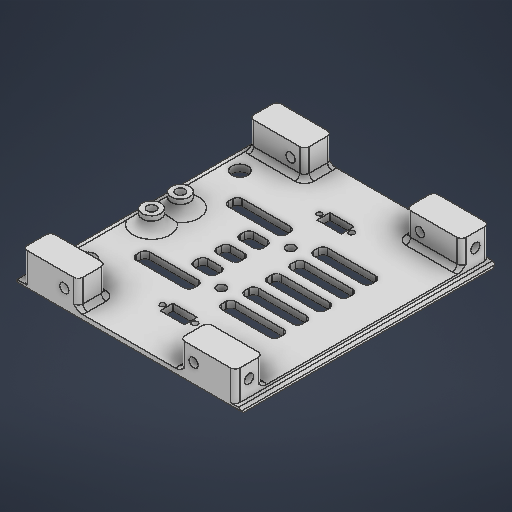
# Autodesk Inventor part: side
Saved by Autodesk Inventor 2026.2 (Build 302298010, 298A)
## iProperties
Created: 2026-05-12
Part Number: side
Material: 일반
Document SubType Name: Modeling
Designer: work
Density: 1 g/cm^3
Appearance: 기본값
Author: work
Autodesk Inventor part; units mm, degrees
ref_plane "YZ Plane" through (0, 0, 0) normal (1, 0, 0) x (0, 1, 0)
ref_plane "XZ Plane" through (0, 0, 0) normal (0, 1, 0) x (-1, 0, 0)
sketch "스케치1" plane through (0, 0, 0) normal (0, 1, 0) x (-1, 0, 0)
  line L0 (92, 0) -> (0, 0)
  line L1 (0, 0) -> (0, -110)
  line L2 (0, -110) -> (92, -110)
  line L3 (92, -110) -> (92, 0)
  line L4 (86, -104) -> (6, -104) construction
  line L5 (6, -104) -> (6, -6) construction
  line L6 (6, -6) -> (86, -6) construction
  line L7 (86, -6) -> (86, -104) construction
  line L8 (0, 0) -> (24, 0)
  line L9 (24, 0) -> (24, -12)
  line L10 (24, -12) -> (0, -12)
  line L11 (0, -12) -> (0, 0)
  line L12 (92, 0) -> (68, 0)
  line L13 (68, 0) -> (68, -12)
  line L14 (68, -12) -> (92, -12)
  line L15 (92, -12) -> (92, 0)
  line L16 (92, -110) -> (68, -110)
  line L17 (68, -110) -> (68, -98)
  line L18 (68, -98) -> (92, -98)
  line L19 (92, -98) -> (92, -110)
  line L20 (0, -110) -> (24, -110)
  line L21 (24, -110) -> (24, -98)
  line L22 (24, -98) -> (0, -98)
  line L23 (0, -98) -> (0, -110)
  line L24 (92, -55) -> (0, -55) construction
  line L25 (46, 0) -> (46, -110) construction
  circle A0 centre (46, -40) radius 2
  circle A1 centre (46, -70) radius 2
  circle A2 centre (86, -88) radius 3.5
  circle A3 centre (86, -22) radius 3.5
  line L26 (52, -32) -> (77, -32)
  line L27 (77, -32) -> (77, -38)
  line L28 (77, -38) -> (52, -38)
  line L29 (52, -38) -> (52, -32)
  line L30 (52, -48) -> (52, -42)
  line L31 (77, -48) -> (52, -48)
  line L32 (52, -42) -> (77, -42)
  line L33 (77, -42) -> (77, -48)
  line L34 (52, -58) -> (52, -52)
  line L35 (77, -58) -> (52, -58)
  line L36 (52, -52) -> (77, -52)
  line L37 (77, -52) -> (77, -58)
  line L38 (52, -68) -> (52, -62)
  line L39 (77, -68) -> (52, -68)
  line L40 (52, -62) -> (77, -62)
  line L41 (77, -62) -> (77, -68)
  line L42 (52, -78) -> (52, -72)
  line L43 (77, -78) -> (52, -78)
  line L44 (52, -72) -> (77, -72)
  line L45 (77, -72) -> (77, -78)
  line L46 (40, -32) -> (15, -32)
  line L47 (15, -32) -> (15, -38)
  line L48 (15, -38) -> (40, -38)
  line L49 (40, -38) -> (40, -32)
  line L50 (40, -48) -> (40, -42)
  line L51 (15, -48) -> (40, -48)
  line L52 (40, -42) -> (15, -42)
  line L53 (15, -42) -> (15, -48)
  line L54 (40, -58) -> (40, -52)
  line L55 (15, -58) -> (40, -58)
  line L56 (40, -52) -> (15, -52)
  line L57 (15, -52) -> (15, -58)
  line L58 (40, -68) -> (40, -62)
  line L59 (15, -68) -> (40, -68)
  line L60 (40, -62) -> (15, -62)
  line L61 (15, -62) -> (15, -68)
  line L62 (40, -78) -> (40, -72)
  line L63 (15, -78) -> (40, -78)
  line L64 (40, -72) -> (15, -72)
  line L65 (15, -72) -> (15, -78)
  point P0 (86, -55)
  point P1 (77, -55)
  point P2 (0, -98)
  dimension "d0" = 6
  dimension "d1" = 6
  dimension "d2" = 24
  dimension "d3" = 12
  dimension "d4" = 24
  dimension "d5" = 12
  dimension "d6" = 24
  dimension "d7" = 12
  dimension "d8" = 24
  dimension "d9" = 12
  dimension "d10" = 98
  dimension "d12" = 80
  dimension "d13" = 6
  dimension "d14" = 6
  dimension "d15" = 4
  dimension "d16" = 4
  dimension "d17" = 30
  dimension "d18" = 15
  dimension "d19" = 7
  dimension "d20" = 10
  dimension "d21" = 7
  dimension "d22" = 10
  dimension "d23" = 25
  dimension "d24" = 6
  dimension "d27" = 10
  dimension "d32" = 15
  constraints: 132 end point, 20 symmetric about line, 14 parallel, 7 horizontal, 7 perpendicular, 6 midpoint, 5 point on line, 4 centre point, 1 coincident, 1 vertical, 32 other
  measures "d0" distance between parallel lines of L1 L5
  measures "d1" distance between parallel lines of L0 L6
  measures "d2" distance of L9.end L10.end
  measures "d3" distance of L8.end L9.end
  measures "d4" distance of L14.end L13.end
  measures "d5" distance of L13.end L12.end
  measures "d6" distance of L17.end L18.end
  measures "d7" distance of L16.end L17.end
  measures "d8" distance of L22.end L21.end
  measures "d9" distance of L21.end L20.end
  measures "d10" distance of L4.start L6.end
  measures "d12" distance of L6.end L5.end
  measures "d13" distance from line of L3 point (86, -55)
  measures "d14" distance between parallel lines of L2 L4
  measures "d15" diameter of A0
  measures "d16" diameter of A1
  measures "d17" distance of A1.centre A0.centre
  measures "d18" distance from line of L24 A1.centre
  measures "d19" diameter of A2
  measures "d20" distance from line of L18 A2.centre
  measures "d21" diameter of A3
  measures "d22" distance from line of L14 A3.centre
  measures "d23" distance of L27.end L28.end
  measures "d24" distance of L26.end L27.end
  measures "d27" distance of L28.end L30.start
  measures "d32" distance between parallel lines of L3 L37
extrude "돌출1" add sketch "스케치1" along normal blind 3 contours L13 L14 L3 L18 L17 L2 L21 L22 L1 L10 L9 L0
extrude "돌출2" add sketch "스케치1" along normal blind 15 contours L3 L14 L13 L0 | L9 L10 L1 L0 | L3 L2 L17 L18 | L22 L21 L2 L1
sketch "스케치2" plane through (0, 0, 0) normal (0, -1, 0) x (1, 0, 0)
  line L0 (-24, -98) -> (-24, -110) projected
  line L1 (-24, -110) -> (-68, -110) projected
  line L2 (-68, -110) -> (-68, -98) projected
  line L3 (-68, -98) -> (-92, -98) projected
  line L4 (-92, -98) -> (-92, -12) projected
  line L5 (-92, -12) -> (-68, -12) projected
  line L6 (-68, -12) -> (-68, 0) projected
  line L7 (-68, 0) -> (-24, 0) projected
  line L8 (-24, 0) -> (-24, -12) projected
  line L9 (-24, -12) -> (0, -12) projected
  line L10 (0, -12) -> (0, -98) projected
  line L11 (0, -98) -> (-24, -98) projected
  circle A0 centre (-46, -40) radius 2 projected
  circle A1 centre (-46, -70) radius 2 projected
  circle A2 centre (-86, -88) radius 3.5 projected
  circle A3 centre (-86, -22) radius 3.5 projected
  line L12 (-15, -32) -> (-40, -32) projected
  line L13 (-40, -32) -> (-40, -38) projected
  line L14 (-40, -38) -> (-15, -38) projected
  line L15 (-15, -38) -> (-15, -32) projected
  line L16 (-15, -48) -> (-15, -42) projected
  line L17 (-15, -42) -> (-40, -42) projected
  line L18 (-40, -42) -> (-40, -48) projected
  line L19 (-40, -48) -> (-15, -48) projected
  line L20 (-40, -72) -> (-40, -78) projected
  line L21 (-40, -78) -> (-15, -78) projected
  line L22 (-15, -78) -> (-15, -72) projected
  line L23 (-15, -72) -> (-40, -72) projected
  line L24 (-40, -62) -> (-40, -68) projected
  line L25 (-40, -68) -> (-15, -68) projected
  line L26 (-15, -68) -> (-15, -62) projected
  line L27 (-15, -62) -> (-40, -62) projected
  line L28 (-40, -58) -> (-15, -58) projected
  line L29 (-15, -58) -> (-15, -52) projected
  line L30 (-15, -52) -> (-40, -52) projected
  line L31 (-40, -52) -> (-40, -58) projected
  line L32 (-52, -78) -> (-52, -72) projected
  line L33 (-52, -72) -> (-77, -72) projected
  line L34 (-77, -72) -> (-77, -78) projected
  line L35 (-77, -78) -> (-52, -78) projected
  line L36 (-52, -68) -> (-52, -62) projected
  line L37 (-52, -62) -> (-77, -62) projected
  line L38 (-77, -62) -> (-77, -68) projected
  line L39 (-77, -68) -> (-52, -68) projected
  line L40 (-52, -58) -> (-52, -52) projected
  line L41 (-52, -52) -> (-77, -52) projected
  line L42 (-77, -52) -> (-77, -58) projected
  line L43 (-77, -58) -> (-52, -58) projected
  line L44 (-52, -48) -> (-52, -42) projected
  line L45 (-52, -42) -> (-77, -42) projected
  line L46 (-77, -42) -> (-77, -48) projected
  line L47 (-77, -48) -> (-52, -48) projected
  line L48 (-52, -32) -> (-77, -32) projected
  line L49 (-77, -32) -> (-77, -38) projected
  line L50 (-77, -38) -> (-52, -38) projected
  line L51 (-52, -38) -> (-52, -32) projected
  line L52 (0, 0) -> (0, -110) projected
  line L53 (-92, 0) -> (0, 0) projected
  line L54 (-92, -110) -> (-92, 0) projected
  line L55 (0, -110) -> (-92, -110) projected
  circle A4 centre (-46, -40) radius 2 projected
  circle A5 centre (-46, -70) radius 2 projected
  circle A6 centre (-86, -88) radius 3.5 projected
  circle A7 centre (-86, -22) radius 3.5 projected
  line L56 (-15, -32) -> (-40, -32) projected
  line L57 (-15, -38) -> (-15, -32) projected
  line L58 (-40, -38) -> (-15, -38) projected
  line L59 (-40, -32) -> (-40, -38) projected
  line L60 (-15, -48) -> (-15, -42) projected
  line L61 (-40, -48) -> (-15, -48) projected
  line L62 (-40, -42) -> (-40, -48) projected
  line L63 (-15, -42) -> (-40, -42) projected
  line L64 (-40, -72) -> (-40, -78) projected
  line L65 (-15, -72) -> (-40, -72) projected
  line L66 (-15, -78) -> (-15, -72) projected
  line L67 (-40, -78) -> (-15, -78) projected
  line L68 (-40, -62) -> (-40, -68) projected
  line L69 (-15, -62) -> (-40, -62) projected
  line L70 (-15, -68) -> (-15, -62) projected
  line L71 (-40, -68) -> (-15, -68) projected
  line L72 (-40, -58) -> (-15, -58) projected
  line L73 (-40, -52) -> (-40, -58) projected
  line L74 (-15, -52) -> (-40, -52) projected
  line L75 (-15, -58) -> (-15, -52) projected
  line L76 (-52, -78) -> (-52, -72) projected
  line L77 (-77, -78) -> (-52, -78) projected
  line L78 (-77, -72) -> (-77, -78) projected
  line L79 (-52, -72) -> (-77, -72) projected
  line L80 (-52, -68) -> (-52, -62) projected
  line L81 (-77, -68) -> (-52, -68) projected
  line L82 (-77, -62) -> (-77, -68) projected
  line L83 (-52, -62) -> (-77, -62) projected
  line L84 (-52, -58) -> (-52, -52) projected
  line L85 (-77, -58) -> (-52, -58) projected
  line L86 (-77, -52) -> (-77, -58) projected
  line L87 (-52, -52) -> (-77, -52) projected
  line L88 (-52, -48) -> (-52, -42) projected
  line L89 (-77, -48) -> (-52, -48) projected
  line L90 (-77, -42) -> (-77, -48) projected
  line L91 (-52, -42) -> (-77, -42) projected
  line L92 (-52, -32) -> (-77, -32) projected
  line L93 (-52, -38) -> (-52, -32) projected
  line L94 (-77, -38) -> (-52, -38) projected
  line L95 (-77, -32) -> (-77, -38) projected
  line L96 (-94.5, -110) -> (2.5, -110)
  line L97 (2.5, -110) -> (2.5, 0)
  line L98 (2.5, 0) -> (-94.5, 0)
  line L99 (-94.5, 0) -> (-94.5, -110)
  dimension "d37" = 2.5
  dimension "d38" = 2.5
  constraints: 8 end point, 2 parallel, 2 point on line, 1 horizontal, 1 perpendicular
  measures "d37" distance between parallel lines of L97 L52
  measures "d38" distance between parallel lines of L99 L4
extrude "돌출3" add sketch "스케치2" against normal blind 2 contours L10 L52 L98 L97 L96 | L96 L99 L98 L54 L4
sketch "스케치3" plane through (-92, 3, -12) normal (-1, 0, 0) x (0, 0, 1)
  line L0 (-98, -1) -> (12, -1) projected
  line L1 (12, -1) -> (12, 12) projected
  line L2 (0, 12) -> (12, 12) projected
  line L3 (0, 0) -> (0, 12) projected
  line L4 (-86, 0) -> (0, 0) projected
  line L5 (-86, 0) -> (-86, 12) projected
  line L6 (-98, 12) -> (-86, 12) projected
  line L7 (-98, -1) -> (-98, 12) projected
  line L8 (12, 0) -> (0, 12) construction
  line L9 (0, 0) -> (12, 12) construction
  circle A0 centre (6, 6) radius 2
  line L10 (-86, 0) -> (0, 0) projected
  line L11 (-43, 0) -> (-43, 34.867) construction
  line L12 (-86, 0) -> (-98, 12) construction
  line L13 (-86, 12) -> (-98, 0) construction
  circle A1 centre (-92, 6) radius 2
  point P0 (12, -3)
  dimension "d41" = 4
  dimension "d42" = 4
  constraints: 10 end point, 4 midpoint, 2 centre point, 2 perpendicular, 2 point on line, 1 vertical
  measures "d41" diameter of A0
  measures "d42" diameter of A1
extrude "돌출4" cut sketch "스케치3" against normal blind 12 contours A0 | A1
sketch "스케치4" plane through (-68, 3, 0) normal (0, 0, 1) x (1, 0, 0)
  circle A0 centre (-6, 6) radius 2
  line L0 (-24, 12) -> (0, 12) projected
  line L1 (0, 0) -> (0, 12) projected
  point P0 (68, -3)
  dimension "d45" = 4
  dimension "d46" = 6
  dimension "d47" = 6
  constraints: 1 centre point
  measures "d45" diameter of A0
  measures "d46" distance from line of L0 A0.centre
  measures "d47" distance from line of L1 A0.centre
extrude "돌출5" cut sketch "스케치4" against normal through all
ref_plane "작업 평면1" through (-46, 0, -110) normal (-1, 0, 0) x (0, 0, 1)
mirror "미러1" about plane through (-46, 0, -110) normal (-1, 0, 0) of "돌출4", "돌출5"
fillet "모깎기1" radius 2 40 edges at (-52, 1.5, -48) (-52, 1.5, -42) (-52, 1.5, -52) (-77, 1.5, -52) (-77, 1.5, -42) (-77, 1.5, -48) (-77, 1.5, -58) (-52, 1.5, -58) (-52, 1.5, -72) (-77, 1.5, -72) (-77, 1.5, -78) (-52, 1.5, -78) (-52, 1.5, -62) (-77, 1.5, -62) (-77, 1.5, -68) (-52, 1.5, -68) (-15, 1.5, -52) (-40, 1.5, -52) (-15, 1.5, -68) (-15, 1.5, -62) (-15, 1.5, -58) (-40, 1.5, -58) (-40, 1.5, -62) (-40, 1.5, -68) (-40, 1.5, -78) (-15, 1.5, -78) (-15, 1.5, -72) (-40, 1.5, -72) (-40, 1.5, -32) (-40, 1.5, -38) (-15, 1.5, -38) (-15, 1.5, -32) (-15, 1.5, -42) (-40, 1.5, -42) (-15, 1.5, -48) (-40, 1.5, -48) (-77, 1.5, -32) (-77, 1.5, -38) (-52, 1.5, -38) (-52, 1.5, -32)
chamfer "모따기1" distance 1 angle 45 4 edges at (-94.5, 0, -55) (-46, 0, -110) (-46, 0, 0) (2.5, 2, -55)
fillet "모깎기3" radius 2 16 edges at (-92, 8.5, 0) (-68, 9, 0) (-68, 9, -12) (-24, 9, 0) (-24, 9, -98) (0, 8.5, 0) (0, 9, -12) (-24, 9, -12) (-92, 9, -12) (-92, 9, -98) (-92, 8.5, -110) (-68, 9, -98) (-68, 9, -110) (-24, 9, -110) (0, 8.5, -110) (0, 9, -98)
sketch "스케치6" plane through (0, 0, 0) normal (0, -1, 0) x (1, 0, 0)
  line L0 (-93.5, -1) -> (2.5, -1) projected
  line L1 (-45.5, -1) -> (-45.5, -109) construction
  line L2 (2.5, -109) -> (-93.5, -109) projected
  line L3 (-38.5, -21) -> (-52.5, -21) construction
  line L4 (0, -10) -> (0, -100) projected
  line L5 (0, -55) -> (-93.5, -55) construction
  line L6 (-93.5, -109) -> (-93.5, -1) projected
  circle A0 centre (-38.5, -21) radius 1.25
  circle A1 centre (-52.5, -21) radius 1.15
  line L7 (-50.75, -18.25) -> (-40.25, -18.25)
  line L8 (-40.25, -18.25) -> (-40.25, -23.75)
  line L9 (-40.25, -23.75) -> (-50.75, -23.75)
  line L10 (-50.75, -23.75) -> (-50.75, -18.25)
  line L11 (-50.75, -18.25) -> (-40.25, -23.75) construction
  line L12 (-40.25, -18.25) -> (-50.75, -23.75) construction
  line L13 (-38.5, -89) -> (-52.5, -89) construction
  circle A2 centre (-38.5, -89) radius 1.25
  circle A3 centre (-52.5, -89) radius 1.15
  line L14 (-50.75, -91.75) -> (-40.25, -91.75)
  line L15 (-40.25, -91.75) -> (-40.25, -86.25)
  line L16 (-40.25, -86.25) -> (-50.75, -86.25)
  line L17 (-50.75, -86.25) -> (-50.75, -91.75)
  line L18 (-50.75, -91.75) -> (-40.25, -86.25) construction
  line L19 (-40.25, -91.75) -> (-50.75, -86.25) construction
  point P0 (0, 0)
  point P1 (-45.5, -21)
  dimension "d60" = 14
  dimension "d61" = 2.5
  dimension "d62" = 2.3
  dimension "d63" = 10.5
  dimension "d64" = 5.5
  dimension "d65" = 20
  constraints: 32 end point, 8 symmetric about line, 7 midpoint, 4 centre point, 4 coincident, 2 horizontal, 2 parallel, 1 perpendicular, 1 point on line, 2 other
  measures "d60" distance of L3.start L3.end
  measures "d61" diameter of A0
  measures "d62" diameter of A1
  measures "d63" distance of L8.end L9.end
  measures "d64" distance of L7.end L8.end
  measures "d65" distance between parallel lines of L0 L3
extrude "돌출7" cut sketch "스케치6" against normal through all
sketch "스케치7" plane through (0, 3, 0) normal (0, 1, 0) x (1, 0, 0)
  line L0 (-65, 45) -> (-85, 45) construction
  line L1 (-85, 45) -> (-85, 65) construction
  line L2 (-85, 65) -> (-65, 65) construction
  line L3 (-65, 65) -> (-65, 45) construction
  line L4 (-65, 45) -> (-85, 65) construction
  line L5 (-85, 45) -> (-65, 65) construction
  circle A0 centre (-85, 61.25) radius 2
  circle A1 centre (-85, 48.75) radius 2
  line L6 (-92, 100) -> (-92, 10) projected
  line L7 (-75, 38) -> (-54, 38) projected
  line L8 (-62, 38) -> (-82, 38)
  line L9 (-82, 38) -> (-82, 72) construction
  line L10 (-82, 72) -> (-62, 72)
  line L11 (-62, 72) -> (-62, 38)
  line L12 (-52, 66) -> (-52, 64) projected
  line L13 (-62, 55) -> (-92, 55) construction
  line L14 (-77, 38) -> (-77, 72)
  circle A2 centre (-85, 48.75) radius 4
  circle A3 centre (-85, 61.25) radius 4
  point P0 (0, 0)
  point P1 (-75, 55)
  point P2 (-52, 64.7085)
  point P3 (-52, 64.3542)
  dimension "d68" = 20
  dimension "d69" = 20
  dimension "d70" = 4
  dimension "d71" = 4
  dimension "d72" = 6.25
  dimension "d73" = 6.25
  dimension "d74" = 7
  dimension "d75" = 20
  dimension "d76" = 34
  dimension "d77" = 10
  dimension "d80" = 5
  dimension "d81" = 8
  dimension "d82" = 8
  constraints: 24 end point, 7 point on line, 4 centre point, 4 midpoint, 4 parallel, 2 coincident, 2 horizontal, 2 perpendicular, 1 vertical
  measures "d68" distance of L1.end L2.end
  measures "d69" distance of L0.end L1.end
  measures "d70" diameter of A0
  measures "d71" diameter of A1
  measures "d72" vertical distance of point (-75, 55) A1.centre
  measures "d73" vertical distance of A0.centre point (-75, 55)
  measures "d74" distance between parallel lines of L6 L1
  measures "d75" distance of L9.end L10.end
  measures "d76" distance of L8.end L9.end
  measures "d77" distance from line of point (-52, 64.354) L11
  measures "d80" distance between parallel lines of L14 L9
  measures "d81" diameter of A2
  measures "d82" diameter of A3
extrude "돌출8" add sketch "스케치7" against normal up to surface (3 mm away) contours L8 L14 L10 L11 L7
extrude "돌출9" add sketch "스케치7" along normal blind 6 contours A2 | A3
fillet "모깎기4" radius 4 2 edges at (-89, 3, -61.25) (-89, 3, -48.75)
fillet "모깎기5" radius 2 26 edges at (-62, 1.5, -58) (-62, 1.5, -68) (-62, 1.5, -62) (-62, 1.5, -52) (-62, 1.5, -42) (-62, 1.5, -48) (-80, 3, -12) (-91.4142, 3, -11.4142) (-68, 3, -6) (-68.5858, 3, -0.5858) (-68.5858, 3, -11.4142) (-0.5858, 3, -11.4142) (-23.4142, 3, -11.4142) (-24, 3, -6) (-23.4142, 3, -0.5858) (-12, 3, -12) (-23.4142, 3, -98.5858) (-24, 3, -104) (-23.4142, 3, -109.4142) (-0.5858, 3, -98.5858) (-12, 3, -98) (-68, 3, -104) (-68.5858, 3, -109.4142) (-80, 3, -98) (-91.4142, 3, -98.5858) (-68.5858, 3, -98.5858)
